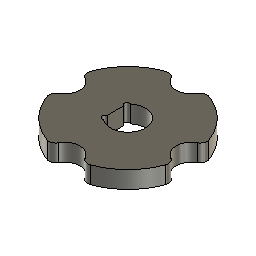
knob_ec12_insert (Autodesk Fusion 360 design; units mm, degrees)
part number: 2026-08-12-11-15-09-215
Autodesk Fusion 360 part; units mm, degrees
sketch "Sketch1" plane through (0, 0, 0) normal (0, 0, 1) x (1, 0, 0)
  circle A0 centre (0, 0) radius 11
  circle A1 centre (0, 11) radius 2.6
  circle A2 centre (-11, 0) radius 2.6
  circle A3 centre (0, -11) radius 2.6
  circle A4 centre (11, 0) radius 2.6
  dimension "d1" = 22
  dimension "d2" = 5.2
  dimension "d3" = 5.2
  dimension "d4" = 5.2
  dimension "d5" = 5.2
  constraint coincident A0.centre origin
  constraint coincident A0 A1.centre
  constraint coincident A0 A2.centre
  constraint coincident A0 A3.centre
  constraint coincident A0 A4.centre
  measures "d1" diameter of A0
  measures "d2" diameter of A1
  measures "d3" diameter of A2
  measures "d4" diameter of A3
  measures "d5" diameter of A4
extrude "Extrude1" add sketch "Sketch1" along normal blind 3 contours A0 A1 A2 A3 A4
fillet "Fillet1" radius 1.2 8 edges at (-10.6927, 2.5818, 1.5) (-10.6927, -2.5818, 1.5) (-2.5818, -10.6927, 1.5) (2.5818, -10.6927, 1.5) (10.6927, -2.5818, 1.5) (10.6927, 2.5818, 1.5) (2.5818, 10.6927, 1.5) (-2.5818, 10.6927, 1.5)
sketch "Sketch2" plane through (0, 0, 3) normal (0, 0, 1) x (-1, 0, 0)
  arc A0 (2.2931, -9.7746) -> (3.7619, -10.3367) centre (3.3515, -9.2091) ccw
  arc A1 (3.7619, -10.3367) -> (10.3367, -3.7619) centre (0, 0) ccw
  arc A2 (10.3367, -3.7619) -> (9.7746, -2.2931) centre (9.2091, -3.3515) ccw
  arc A3 (9.7746, 2.2931) -> (9.7746, -2.2931) centre (11, 0) ccw
  arc A4 (9.7746, 2.2931) -> (10.3367, 3.7619) centre (9.2091, 3.3515) ccw
  arc A5 (10.3367, 3.7619) -> (3.7619, 10.3367) centre (0, 0) ccw
  arc A6 (3.7619, 10.3367) -> (2.2931, 9.7746) centre (3.3515, 9.2091) ccw
  arc A7 (-2.2931, 9.7746) -> (2.2931, 9.7746) centre (0, 11) ccw
  arc A8 (-2.2931, 9.7746) -> (-3.7619, 10.3367) centre (-3.3515, 9.2091) ccw
  arc A9 (-3.7619, 10.3367) -> (-10.3367, 3.7619) centre (0, 0) ccw
  arc A10 (-10.3367, 3.7619) -> (-9.7746, 2.2931) centre (-9.2091, 3.3515) ccw
  arc A11 (-9.7746, -2.2931) -> (-9.7746, 2.2931) centre (-11, 0) ccw
  arc A12 (-9.7746, -2.2931) -> (-10.3367, -3.7619) centre (-9.2091, -3.3515) ccw
  arc A13 (-10.3367, -3.7619) -> (-3.7619, -10.3367) centre (0, 0) ccw
  arc A14 (-3.7619, -10.3367) -> (-2.2931, -9.7746) centre (-3.3515, -9.2091) ccw
  arc A15 (2.2931, -9.7746) -> (-2.2931, -9.7746) centre (0, -11) ccw
  line L0 (2.2244, 2.05) -> (2.2244, -2.05)
  line L1 (0, 0) -> (2.2244, 2.05)
  circle A16 centre (0, 0) radius 3.025
  circle A17 centre (2.0774, 1.9145) radius 0.5
  circle A18 centre (2.0774, -1.9145) radius 0.5
  line L2 (0, 0) -> (2.2244, -2.05)
  dimension "d10" = 6.05
  dimension "d11" = 4.1
  dimension "d12" = 1
  dimension "d13" = 0.2
  dimension "d14" = 1
  dimension "d15" = 0.2
  constraint coincident L0.start A16
  constraint coincident L0.end A16
  constraint vertical L0
  constraint coincident A1.centre A5.centre
  constraint coincident A17.centre L1
  constraint coincident A18.centre L2
  measures "d10" diameter of A16
  measures "d11" distance of L0.start L0.end
  measures "d12" diameter of A17
  measures "d13" distance of L0.start A17.centre
  measures "d14" diameter of A18
  measures "d15" distance of L0.end A18.centre
extrude "Extrude2" cut sketch "Sketch2" against normal blind 3 contours L0 A16 A17 | L0 L1 A17 | A16 A17 | L1 A16 A17 | L0 L1 A17 A18 L2 | L1 A16 A17 A18 L2 | L0 A16 A18 | L0 A18 L2 | A16 A18 L2 | A16 A18
